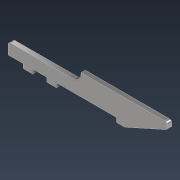
# Autodesk Inventor part: SP31V1 Columna Freno
Saved by Autodesk Inventor 2021.2 (Build 252289000, 289)
## iProperties
Created: 2026-06-23
Part Number: SP31V1 Columna Freno
Material: Stainless Steel
Document SubType Name: Sheet Metal
Designer: nelso
Density: 8.08 g/cm^3
Sheet Metal Rule: Default_mm
Appearance: Semi-Polished
Mass: 29.9021 g
Surface Area: 31.6026 cm^2
Volume: 3.70076 cm^3
Author: nelso
Autodesk Inventor part; units mm, degrees
ref_plane "YZ Plane" through (0, 0, 0) normal (1, 0, 0) x (0, 1, 0)
ref_plane "XZ Plane" through (0, 0, 0) normal (0, 1, 0) x (-1, 0, 0)
ref_plane "XY Plane" through (0, 0, 0) normal (0, 0, 1) x (1, 0, 0)
sketch "Sketch1" plane through (0, 0, 0) normal (0, 0, 1) x (1, 0, 0)
  line L0 (58, -6.1405) -> (122, -6.1405)
  line L1 (122, -6.1405) -> (122, -10.6498)
  line L2 (4.088, -21.6998) -> (15.288, -21.6998)
  line L3 (15.288, -21.6998) -> (15.288, -24.8998)
  line L4 (15.288, -24.8998) -> (22.788, -24.8998)
  line L5 (22.788, -24.8998) -> (22.788, -21.6998)
  line L6 (32.788, -21.6998) -> (32.788, -24.8998)
  line L7 (40.288, -24.8998) -> (40.288, -21.6998)
  line L8 (58, -6.1405) -> (122, -6.1405)
  line L9 (122, -6.1405) -> (122, -10.6498)
  line L10 (90.288, -21.6998) -> (40.288, -21.6998)
  line L11 (40.288, -24.8998) -> (40.288, -21.6998)
  line L12 (40.288, -24.8998) -> (32.788, -24.8998)
  line L13 (32.788, -24.8998) -> (32.788, -21.6998)
  line L14 (32.788, -21.6998) -> (22.788, -21.6998)
  line L15 (22.788, -24.8998) -> (22.788, -21.6998)
  line L16 (15.288, -24.8998) -> (22.788, -24.8998)
  line L17 (15.288, -24.8998) -> (15.288, -21.6998)
  line L18 (15.288, -21.6998) -> (4.088, -21.6998)
  line L19 (58, -6.1405) -> (58, -13.1405)
  line L20 (4.088, -21.6998) -> (4.088, -13.1405)
  line L21 (4.088, -13.1405) -> (58, -13.1405)
  line L22 (90.288, -21.6998) -> (84.288, -21.6998)
  line L23 (84.288, -21.6998) -> (84.288, -24.8998)
  line L24 (84.288, -24.8998) -> (90.288, -24.8998)
  line L25 (90.288, -24.8998) -> (90.288, -21.6998)
  line L26 (122, -10.6498) -> (90.288, -24.8998)
  point P0 (0, 0)
  point P1 (0, 0)
  dimension "d1" = 11.2
  dimension "d2" = 7.5
  dimension "d3" = 10
  dimension "d4" = 7.5
  dimension "d15" = 21.6998
  dimension "d20" = 7
  dimension "d21" = 58
  dimension "d22" = 122
  dimension "d25" = 50
  dimension "d27" = 4.088
  dimension "d32" = 6
  measures "d1" distance of L2.start L2.end
  measures "d2" distance of L3.end L4.end
  measures "d3" distance of L5.end L6.start
  measures "d4" distance of L6.end L7.start
  measures "d15" distance from line of L2 point (0, 0)
  measures "d20" distance of L0.start L19.end
  measures "d21" distance from line of L19 point (0, 0)
  measures "d22" distance from line of point (0, 0) L1
  measures "d25" distance of L10.start L7.end
  measures "d27" horizontal distance of L2.start point (0, 0)
  measures "d32" distance of L24.end L23.end
extrude "Plate1" add sketch "Sketch1" along normal mid plane 3.2
fillet "Corner Round3" radius 6 1 edges at (58, -13.1405, 0)
fillet "Corner Round4" radius 2 4 edges at (122, -6.1405, 0) (122, -10.6498, 0) (4.088, -13.1405, 0) (90.288, -24.8998, 0)
fillet "Corner Round5" radius 0.5 6 edges at (4.088, -21.6998, 0) (15.288, -24.8998, 0) (22.788, -24.8998, 0) (32.788, -24.8998, 0) (40.288, -24.8998, 0) (84.288, -24.8998, 0)
equation "\"d4\" = d2"
equation "\"d0\" = Thickness"
equation "\"BendRadius\" = Thickness"
equation "\"BendReliefWidth\" = Thickness"
equation "\"BendReliefDepth\" = 0.5 * Thickness"
equation "\"CornerReliefSize\" = 4 * Thickness"
equation "\"MinimumRemnant\" = 2 * Thickness"
equation "\"TransitionRadius\" = BendRadius"
equation "\"JacobiRadiusSize\" = BendRadius"
equation "\"GapSize\" = Thickness"
equation "\"Thickness\" = 3.2"
body "Solid1"
